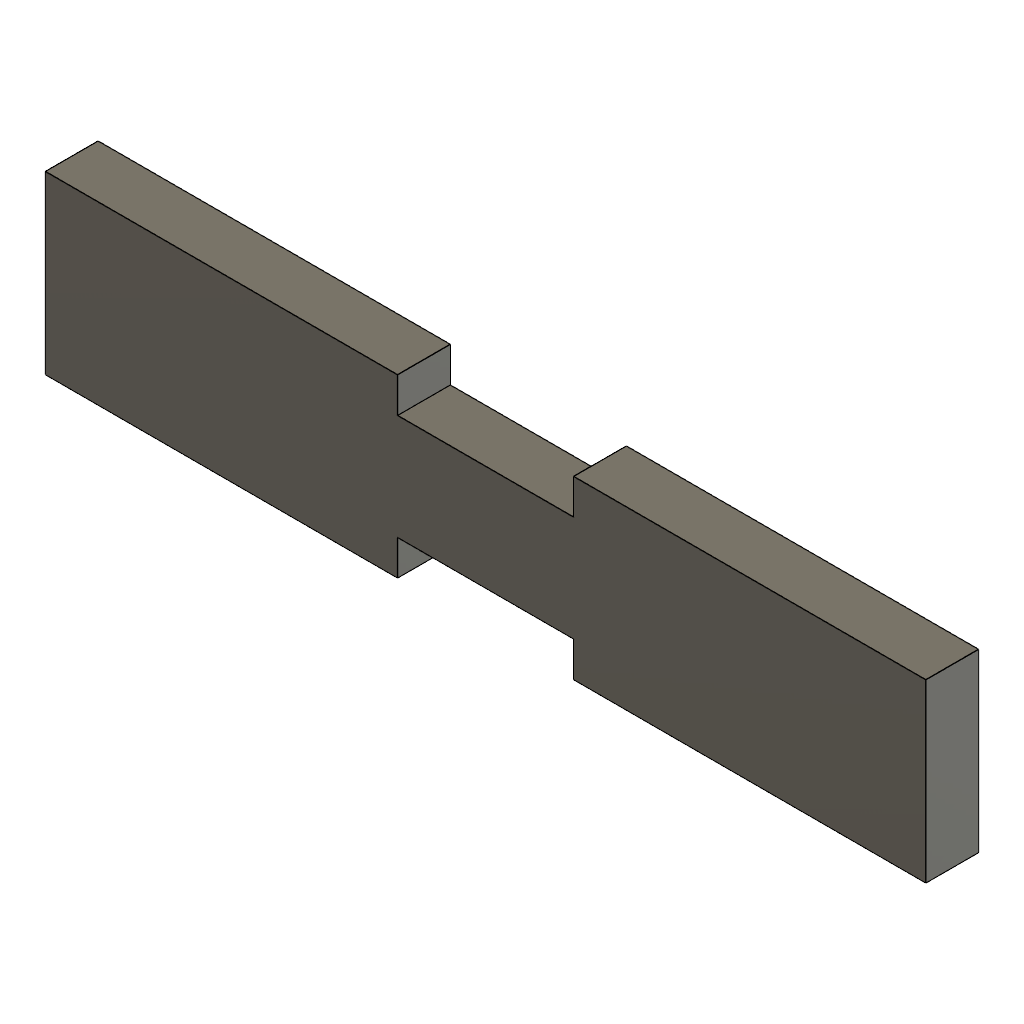
multi_body_join_extrude (Autodesk Fusion 360 design; units mm, degrees)
part number: 2026-11-13-14-48-32-625
Autodesk Fusion 360 part; units mm, degrees
sketch "Sketch1" plane through (0, 0, 0) normal (0, 0, 1) x (1, 0, 0)
  line L0 (0, 0) -> (20, 0)
  line L1 (20, 0) -> (20, 10)
  line L2 (20, 10) -> (0, 10)
  line L3 (0, 10) -> (0, 0)
extrude "Extrude1" add sketch "Sketch1" along normal blind 3 makes body 1
sketch "Sketch2" plane through (0, 0, 0) normal (0, 0, 1) x (1, 0, 0)
  line L0 (30, 0) -> (50, 0)
  line L1 (50, 0) -> (50, 10)
  line L2 (50, 10) -> (30, 10)
  line L3 (30, 10) -> (30, 0)
extrude "Extrude2" add sketch "Sketch2" along normal blind 3 separate body makes body 2
ref_plane "WorkPlane1" through (0, 0, 3) normal (0, 0, 1) x (1, 0, 0)
sketch "Sketch3" plane through (0, 0, 3) normal (0, 0, 1) x (1, 0, 0)
  line L0 (15, 2) -> (35, 2)
  line L1 (35, 2) -> (35, 8)
  line L2 (35, 8) -> (15, 8)
  line L3 (15, 8) -> (15, 2)
extrude "Extrude3" add sketch "Sketch3" against normal blind 3 bodies 1 2
